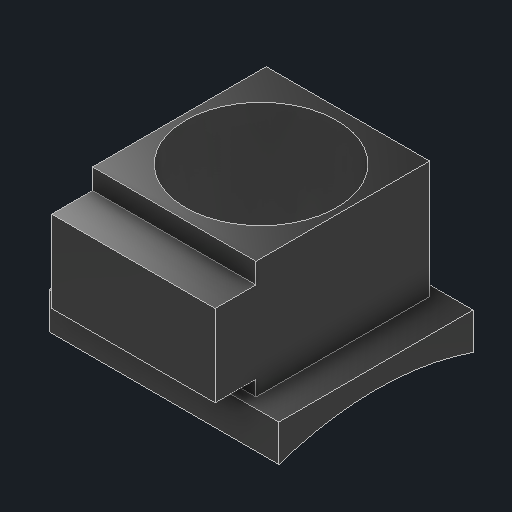
# Autodesk Inventor part: c8n_focuser_body
Saved by Autodesk Inventor 2027.1 (Build 311270010, 270A)
## iProperties
Created: 2026-11-04
Part Number: c8n_focuser_body
Material: Generic
Description: 2 in rack and pinion focuser body
Document SubType Name: Modeling
Designer: Claude (from photos)
Density: 1 g/cm^3
Appearance: Glossy - Black
Author: alexg
Autodesk Inventor part; units mm, degrees
ref_plane "Work Plane1" through (0, 100, 0) normal (0, 1, 0) x (-1, 0, 0)
sketch "Base saddle sketch" plane through (0, 100, 0) normal (0, 1, 0) x (-1, 0, 0)
  line L0 (-797, -38) -> (-887, -38)
  line L1 (-887, -38) -> (-887, 38)
  line L2 (-887, 38) -> (-797, 38)
  line L3 (-797, 38) -> (-797, -38)
  constraints: 8 end point, 2 parallel, 1 horizontal, 1 perpendicular
extrude "Base saddle" add sketch "Base saddle sketch" along normal blind 24
ref_plane "Work Plane2" through (782, 0, 0) normal (1, 0, 0) x (0, 1, 0)
sketch "Fit to tube sketch" plane through (782, 0, 0) normal (1, 0, 0) x (0, 1, 0)
  circle A0 centre (0, 0) radius 116
  constraints: 1 centre point
extrude "Fit to tube" cut sketch "Fit to tube sketch" along normal blind 120
ref_plane "Work Plane3" through (0, 124, 0) normal (0, 1, 0) x (-1, 0, 0)
sketch "Body sketch" plane through (0, 124, 0) normal (0, 1, 0) x (-1, 0, 0)
  line L0 (-810, -34) -> (-874, -34)
  line L1 (-874, -34) -> (-874, 34)
  line L2 (-874, 34) -> (-810, 34)
  line L3 (-810, 34) -> (-810, -34)
  constraints: 8 end point, 2 parallel, 1 horizontal, 1 perpendicular
extrude "Body" add sketch "Body sketch" along normal blind 46
ref_plane "Work Plane4" through (0, 130, 0) normal (0, 1, 0) x (-1, 0, 0)
sketch "Pinion housing sketch" plane through (0, 130, 0) normal (0, 1, 0) x (-1, 0, 0)
  line L0 (-810, 34) -> (-874, 34)
  line L1 (-874, 34) -> (-874, 50)
  line L2 (-874, 50) -> (-810, 50)
  line L3 (-810, 50) -> (-810, 34)
  constraints: 8 end point, 2 parallel, 1 horizontal, 1 perpendicular
extrude "Pinion housing" add sketch "Pinion housing sketch" along normal blind 32
ref_plane "Work Plane5" through (0, 90, 0) normal (0, 1, 0) x (-1, 0, 0)
sketch "Drawtube bore sketch" plane through (0, 90, 0) normal (0, 1, 0) x (-1, 0, 0)
  circle A0 centre (-842, 0) radius 29.6
  constraints: 1 centre point
extrude "Drawtube bore" cut sketch "Drawtube bore sketch" along normal blind 100
ref_plane "Work Plane6" through (0, 0, -34) normal (0, 0, 1) x (1, 0, 0)
sketch "Lock screw sketch" plane through (0, 0, -34) normal (0, 0, 1) x (1, 0, 0)
  circle A0 centre (842, 150) radius 3
  constraints: 1 centre point
extrude "Lock screw" add sketch "Lock screw sketch" against normal blind 4
ref_plane "Work Plane7" through (0, 0, -38) normal (0, 0, 1) x (1, 0, 0)
sketch "Lock knob sketch" plane through (0, 0, -38) normal (0, 0, 1) x (1, 0, 0)
  line L0 (850, 150) -> (849.0513, 151.8894)
  line L1 (849.0513, 151.8894) -> (848.9282, 154)
  line L2 (848.9282, 154) -> (847.1619, 155.1619)
  line L3 (847.1619, 155.1619) -> (846, 156.9282)
  line L4 (846, 156.9282) -> (843.8894, 157.0513)
  line L5 (843.8894, 157.0513) -> (842, 158)
  line L6 (842, 158) -> (840.1106, 157.0513)
  line L7 (840.1106, 157.0513) -> (838, 156.9282)
  line L8 (838, 156.9282) -> (836.8381, 155.1619)
  line L9 (836.8381, 155.1619) -> (835.0718, 154)
  line L10 (835.0718, 154) -> (834.9487, 151.8894)
  line L11 (834.9487, 151.8894) -> (834, 150)
  line L12 (834, 150) -> (834.9487, 148.1106)
  line L13 (834.9487, 148.1106) -> (835.0718, 146)
  line L14 (835.0718, 146) -> (836.8381, 144.8381)
  line L15 (836.8381, 144.8381) -> (838, 143.0718)
  line L16 (838, 143.0718) -> (840.1106, 142.9487)
  line L17 (840.1106, 142.9487) -> (842, 142)
  line L18 (842, 142) -> (843.8894, 142.9487)
  line L19 (843.8894, 142.9487) -> (846, 143.0718)
  line L20 (846, 143.0718) -> (847.1619, 144.8381)
  line L21 (847.1619, 144.8381) -> (848.9282, 146)
  line L22 (848.9282, 146) -> (849.0513, 148.1106)
  line L23 (849.0513, 148.1106) -> (850, 150)
  constraints: 48 end point
extrude "Lock knob" add sketch "Lock knob sketch" against normal blind 8
body "Solid1"
